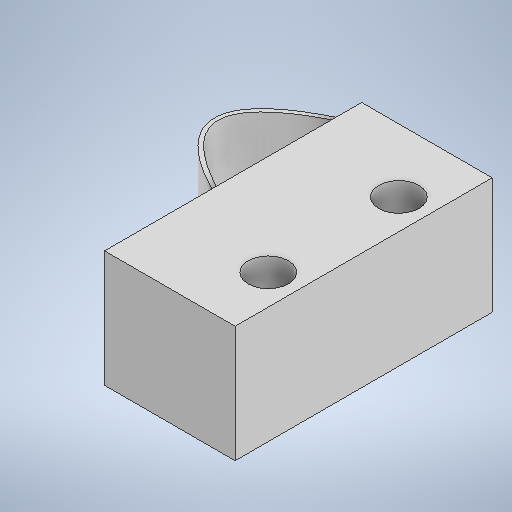
# Autodesk Inventor part: krańcówka
Saved by Autodesk Inventor 2025.2 (Build 292293000, 293)
## iProperties
Created: 2025-04-08
Part Number: krańcówka
Material: Ogólny
Document SubType Name: Modeling
Designer: Jan Bołtralik
Density: 1 g/cm^3
Appearance: Domyślna
Author: Jan Bołtralik
Autodesk Inventor part; units mm, degrees
ref_plane "YZ Plane" through (0, 0, 0) normal (1, 0, 0) x (0, 1, 0)
ref_plane "XZ Plane" through (0, 0, 0) normal (0, 1, 0) x (-1, 0, 0)
sketch "Szkic1" plane through (0, 0, 0) normal (0, 1, 0) x (-1, 0, 0)
  line L0 (0, 0) -> (6.5, 0)
  line L1 (6.5, 0) -> (6.5, -12.8)
  line L2 (6.5, -12.8) -> (0, -12.8)
  line L3 (0, -12.8) -> (0, 0)
  circle A0 centre (1.5, -3.15) radius 1
  circle A1 centre (1.5, -9.65) radius 1
  dimension "d0" = 6.5
  dimension "d1" = 12.8
  dimension "d2" = 2
  dimension "d3" = 2
  dimension "d4" = 1.5
  dimension "d5" = 1.5
  dimension "d6" = 6.5
  dimension "d7" = 3.15
  constraints: 8 end point, 2 centre point, 2 parallel, 1 horizontal, 1 perpendicular
  measures "d0" distance of L1.end L2.end
  measures "d1" distance of L0.end L1.end
  measures "d2" diameter of A0
  measures "d3" diameter of A1
  measures "d4" distance from line of L3 A1.centre
  measures "d5" distance from line of L3 A0.centre
  measures "d6" distance of A1.centre A0.centre
  measures "d7" distance from line of L2 A1.centre
extrude "Wyciągnięcie proste1" add sketch "Szkic1" along normal blind 5.8
ref_plane "Płaszczyzna konstrukcyjna1" through (0, 2.9, 0) normal (0, -1, 0) x (1, 0, 0)
sketch "Szkic2" plane through (0, 2.9, 0) normal (0, -1, 0) x (1, 0, 0)
  line L0 (0, 0) -> (0, -12.8) projected
  spline S0 degree 2 poles (-7.3, -6.4) (-13.8472, -9.6739) (-7, -12.8) knots 0 0 0 1 1 1
  arc A0 (-6.5, -3.2) -> (-6.7, -3.4) centre (-6.5, -3.4) ccw
  arc A1 (-7.3, -6.4) -> (-7.101, -6.2198) centre (-7.3, -6.2) ccw
  line L1 (-6.7, -3.4) -> (-7.0907, -6.1349)
  arc A2 (-7.0907, -6.1349) -> (-7.101, -6.2198) centre (-5.1108, -6.4178) ccw
  point P0 (-10.4999, -9.5993)
  point P1 (-7.1, -6.2)
  dimension "d17" = 2
  constraints: 7 point on circle, 3 centre point, 2 end point, 2 tangent, 1 point on line, 3 other
  measures "d17" radius of A2
sketch "Szkic3" plane through (-6.5, 0, -12.8) normal (-1, 0, 0) x (0, 0, 1)
  line L0 (9.4, 2.9) -> (9.6, 2.9) projected
  line L1 (9.7, 4.7) -> (9.5, 4.7)
  line L2 (9.5, 4.7) -> (9.5, 1.1)
  line L3 (9.5, 1.1) -> (9.7, 1.1)
  line L4 (9.7, 1.1) -> (9.7, 4.7)
  line L5 (9.7, 4.7) -> (9.5, 1.1) construction
  line L6 (9.5, 4.7) -> (9.7, 1.1) construction
  dimension "d18" = 0.2
  dimension "d19" = 3.6
  constraints: 12 end point, 2 midpoint, 2 parallel, 1 horizontal, 1 perpendicular
  measures "d18" distance of L3.end L2.end
  measures "d19" distance of L2.end L1.end
sweep "Przeciągnięcie1" add profiles "Szkic3" path "Szkic2" path curves A0 L1 A2 A1 S0
